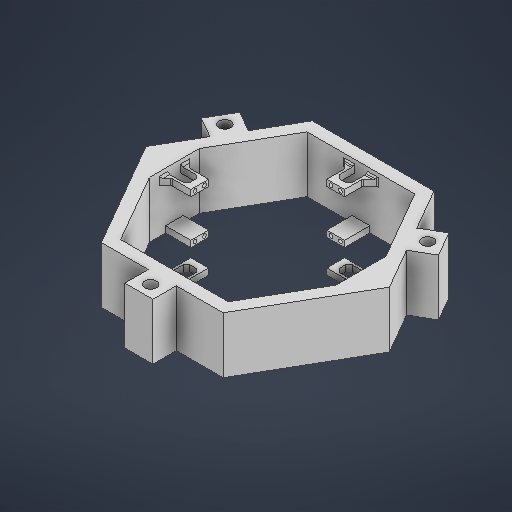
# Autodesk Inventor part: Control Ring
Saved by Autodesk Inventor 2026.3 (Build 303398000, 398)
## iProperties
Created: 2026-06-26
Part Number: Control Ring
Material: Generic
Document SubType Name: Modeling
Designer: joaqu
Density: 1 g/cm^3
Appearance: Default
Author: joaqu
Autodesk Inventor part; units mm, degrees
ref_plane "YZ Plane" through (0, 0, 0) normal (1, 0, 0) x (0, 1, 0)
ref_plane "XZ Plane" through (0, 0, 0) normal (0, 1, 0) x (-1, 0, 0)
ref_plane "XY Plane" through (0, 0, 0) normal (0, 0, 1) x (1, 0, 0)
sketch "Sketch1" plane through (0, 0, 0) normal (0, 1, 0) x (-1, 0, 0)
  line L0 (-115, 0) -> (-57.5, 99.5929)
  line L1 (-57.5, 99.5929) -> (57.5, 99.5929)
  line L2 (57.5, 99.5929) -> (115, 0)
  line L3 (115, 0) -> (57.5, -99.5929)
  line L4 (57.5, -99.5929) -> (-57.5, -99.5929)
  line L5 (-57.5, -99.5929) -> (-115, 0)
  line L6 (-130, 0) -> (-65, 112.5833)
  line L7 (-65, 112.5833) -> (65, 112.5833)
  line L8 (65, 112.5833) -> (130, 0)
  line L9 (130, 0) -> (65, -112.5833)
  line L10 (65, -112.5833) -> (-65, -112.5833)
  line L11 (-65, -112.5833) -> (-130, 0)
  point P0 (0, 0)
  point P1 (0, 0)
  point P2 (0, 0)
  dimension "d0" = 115
  dimension "d2" = 130
  constraints: 24 end point, 2 coincident, 26 other
  measures "d0" distance of L3.end L4.end
  measures "d2" distance of L9.end L10.end
extrude "Extrusion1" add sketch "Sketch1" along normal blind 60
sketch "Sketch15" plane through (-57.5, 0, -99.5929) normal (0, 0, 1) x (1, 0, 0)
  line L0 (0, 0) -> (115, 0) projected
  line L1 (57.5, 0) -> (60.85, 0)
  line L2 (57.5, 0) -> (48, 0)
  line L3 (57.5, 0) -> (67, 0)
  line L4 (67, 0) -> (67, 6.7)
  line L5 (67, 6.7) -> (48, 6.7)
  line L6 (48, 6.7) -> (48, 0)
  dimension "d77" = 9.5
  dimension "d78" = 9.5
  dimension "d80" = 6.7
  constraints: 12 end point, 3 point on line, 2 perpendicular, 1 vertical
  measures "d77" distance of L1.start L2.end
  measures "d78" distance of L1.start L3.end
  measures "d80" distance of L3.end L4.end
extrude "Extrusion10" add sketch "Sketch15" along normal blind 27
sketch "Sketch18" plane through (-57.5, 0, -72.5929) normal (0, 0, 1) x (1, 0, 0)
  line L0 (67, 6.7) -> (48, 6.7) projected
  line L1 (48, 6.7) -> (48, 0) projected
  circle A0 centre (52.5, 3.35) radius 2
  circle A1 centre (62.5, 3.35) radius 2
  point P0 (57.5, 0)
  dimension "d91" = 4
  dimension "d94" = 4
  constraints: 2 centre point
  measures "d91" diameter of A0
  measures "d94" diameter of A1
extrude "Extrusion12" cut sketch "Sketch18" against normal blind 4
pattern_linear "Rectangular Pattern1" count 2 spacing 47 along (0, 1, 0) of "Extrusion10", "Extrusion12"
sketch "Sketch24" plane through (-9.5, 53.7, -99.5929) normal (0, 1, 0) x (1, 0, 0)
  line L0 (0, 0) -> (19, 0) projected
  line L1 (3.7711, 0) -> (1.2289, 0)
  line L2 (0, 0) -> (0, -27) projected
  line L3 (2.5, 0) -> (2.5, -19.9491)
  line L4 (2.5, -19.9491) -> (16.5, -19.9491)
  line L5 (16.5, -19.9491) -> (16.5, 0)
  line L6 (16.5, 0) -> (2.5, 0)
  line L7 (19, 0) -> (19, -27) projected
  point P0 (9.5, -99.5929)
  point P1 (16.5, 0)
  point P2 (2.5, 0)
  dimension "d120" = 2.5
  dimension "d121" = 2.5
  constraints: 10 end point, 2 parallel, 2 perpendicular, 2 point on line, 1 midpoint
  measures "d120" distance between parallel lines of L2 L3
  measures "d121" distance between parallel lines of L7 L5
extrude "Extrusion16" cut sketch "Sketch24" against normal blind 10
chamfer "Chamfer2" distance 8.35 angle 45 1 edges at (9.5, 50.35, -99.5929)
chamfer "Chamfer3" distance 8.35 angle 45 1 edges at (-9.5, 50.35, -99.5929)
chamfer "Chamfer4" distance 2 angle 45 2 edges at (13.675, 53.7, -99.5929) (8.25, 53.7, -99.5929)
chamfer "Chamfer5" distance 2 angle 45 2 edges at (-13.675, 53.7, -99.5929) (-8.25, 53.7, -99.5929)
fillet "Fillet1" radius 2 1 edges at (9.5, 50.35, -91.2429)
fillet "Fillet2" radius 2 2 edges at (17.85, 54.7, -99.5929) (17.85, 50.35, -99.5929)
fillet "Fillet3" radius 2 2 edges at (12.675, 53.7, -97.5929) (8.25, 53.7, -97.5929)
fillet "Fillet4" radius 2 1 edges at (-11.425, 53.7, -97.5929)
fillet "Fillet5" radius 2 2 edges at (-17.85, 54.7, -99.5929) (-17.85, 50.35, -99.5929)
fillet "Fillet6" radius 2 1 edges at (-9.5, 50.35, -91.2429)
chamfer "Chamfer6" distance 3.5875 angle 45 1 edges at (-7, 50.35, -79.6438)
chamfer "Chamfer7" distance 3.5875 angle 45 1 edges at (7, 50.35, -79.6438)
pattern_circular "Circular Pattern6" count 4 over 360 about axis through (0, -10, 0) along (0, 1, 0) of "Extrusion16", "Extrusion10", "Extrusion12", "Rectangular Pattern1", "Chamfer6", "Chamfer7"
sketch "Sketch26" plane through (0, 0, 0) normal (0, -1, 0) x (1, 0, 0)
  line L0 (-99.5929, 9.5) -> (-99.5929, -9.5) projected
  line L1 (-99.5929, -9.5) -> (-99.5929, -26.6858)
  line L2 (-115, 0) -> (-57.5, -99.5929) projected
  line L3 (-115, 0) -> (-99.5929, 26.6858)
  line L4 (-57.5, 99.5929) -> (-115, 0) projected
  line L5 (-99.5929, 9.5) -> (-72.5929, 9.5) projected
  line L6 (-99.5929, 9.5) -> (-99.5929, 26.6858)
  line L7 (-99.5929, -9.5) -> (-99.5929, 9.5)
  point P0 (0, 0)
  constraints: 8 end point, 3 point on line, 2 perpendicular, 1 vertical
extrude "Extrusion18" add sketch "Sketch26" against normal up to surface (60 mm away)
chamfer "Chamfer8" distance 6.7625 angle 45 1 edges at (-99.5929, 50.35, 9.5)
chamfer "Chamfer9" distance 6.7625 angle 45 1 edges at (-99.5929, 50.35, -9.5)
chamfer "Chamfer10" distance 6.7625 angle 45 1 edges at (9.5, 50.35, 99.5929)
chamfer "Chamfer11" distance 6.7625 angle 45 1 edges at (-9.5, 50.35, 99.5929)
mirror "Mirror3" about plane through (0, 0, 0) normal (1, 0, 0) of "Extrusion18"
chamfer "Chamfer12" distance 6.7625 angle 45 1 edges at (99.5929, 50.35, -9.5)
chamfer "Chamfer13" distance 6.7625 angle 45 1 edges at (99.5929, 50.35, 9.5)
chamfer "Chamfer14" distance 2 angle 45 1 edges at (-99.5929, 53.7, 11.6313)
chamfer "Chamfer15" distance 2 angle 45 1 edges at (-99.5929, 53.7, -11.6313)
chamfer "Chamfer16" distance 2 angle 45 2 edges at (99.5929, 53.7, -12.8812) (99.5929, 53.7, -8.25)
chamfer "Chamfer17" distance 2 angle 45 2 edges at (99.5929, 53.7, 12.8813) (99.5929, 53.7, 8.25)
chamfer "Chamfer18" distance 2 angle 45 1 edges at (11.6312, 53.7, 99.5929)
chamfer "Chamfer19" distance 2 angle 45 1 edges at (-11.6313, 53.7, 99.5929)
fillet "Fillet7" radius 2 1 edges at (-92.8304, 50.35, 9.5)
fillet "Fillet8" radius 2 1 edges at (-92.8304, 50.35, -9.5)
fillet "Fillet9" radius 2 1 edges at (9.5, 50.35, 92.8304)
fillet "Fillet10" radius 2 1 edges at (-9.5, 50.35, 92.8304)
fillet "Fillet11" radius 2 1 edges at (92.8304, 50.35, 9.5)
fillet "Fillet12" radius 2 1 edges at (92.8304, 50.35, -9.5)
sketch "Sketch27" plane through (0, 60, 0) normal (0, 1, 0) x (1, 0, 0)
  line L0 (9.5, -99.5929) -> (-9.5, -99.5929) projected
  line L1 (0, -137.5829) -> (15, -137.5829)
  line L2 (15, -137.5829) -> (15, -99.5929)
  line L3 (7, -99.5929) -> (16.2625, -99.5929) projected
  line L4 (0, -99.5929) -> (-15, -99.5929)
  line L5 (-15, -99.5929) -> (-15, -137.5829)
  line L6 (-15, -137.5829) -> (0, -137.5829)
  point P0 (0, 0)
  dimension "d202" = 37.99
  dimension "d203" = 15
  dimension "d204" = 15
  constraints: 10 end point, 3 perpendicular, 3 point on line, 1 midpoint
  measures "d202" distance of L4.start L1.start
  measures "d203" distance of L1.start L1.end
  measures "d204" distance of L4.start L4.end
extrude "Extrusion19" add sketch "Sketch27" against normal up to surface (60 mm away)
sketch "Sketch28" plane through (0, 60, 0) normal (0, 1, 0) x (1, 0, 0)
  line L0 (-15, -137.5829) -> (15, -137.5829) projected
  line L1 (0, -137.5829) -> (0, -125.0829)
  circle A0 centre (0, -125.0829) radius 6.25
  point P0 (0, 0)
  dimension "d207" = 12.5
  dimension "d208" = 12.5
  constraints: 2 end point, 1 centre point, 1 coincident, 1 midpoint, 1 vertical
  measures "d207" distance of L1.start L1.end
  measures "d208" diameter of A0
extrude "Extrusion20" cut sketch "Sketch28" against normal up to surface (60 mm away)
pattern_circular "Circular Pattern7" count 3 over 360 about axis through (0, -10, 0) along (0, 1, 0) of "Extrusion19", "Extrusion20"
body "Solid1"
